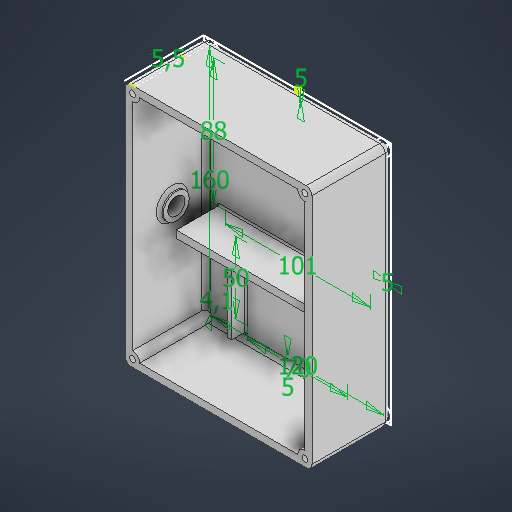
# Autodesk Inventor part: CaseBitDogLabV2
Saved by Autodesk Inventor 2027 (Build 310192000, 192)
## iProperties
Created: 2026-10-24
Part Number: CaseBitDogLabV2
Material: Genérico
Document SubType Name: Modeling
Designer: EspacoMaker
Density: 1 g/cm^3
Appearance: Padrão
Author: EspacoMaker
Autodesk Inventor part; units mm, degrees
ref_plane "YZ Plane" through (0, 0, 0) normal (1, 0, 0) x (0, 1, 0)
ref_plane "XZ Plane" through (0, 0, 0) normal (0, 1, 0) x (-1, 0, 0)
ref_plane "XY Plane" through (0, 0, 0) normal (0, 0, 1) x (1, 0, 0)
sketch "Esboço1" plane through (0, 0, 0) normal (0, 0, 1) x (1, 0, 0)
  line L0 (60, 80) -> (-60, 80)
  line L1 (-60, 80) -> (-60, -80)
  line L2 (-60, -80) -> (60, -80)
  line L3 (60, -80) -> (60, 80)
  line L4 (60, 80) -> (-60, -80) construction
  line L5 (-60, 80) -> (60, -80) construction
  line L6 (0, 80) -> (0, -80) construction
  line L7 (65, 85) -> (-65, 85)
  line L8 (-65, 85) -> (-65, -85)
  line L9 (-65, -85) -> (65, -85)
  line L10 (65, -85) -> (65, 85)
  line L11 (50.5, 75) -> (-50.5, 75) construction
  line L12 (-50.5, 75) -> (-50.5, -13) construction
  line L13 (-50.5, -13) -> (50.5, -13) construction
  line L14 (50.5, -13) -> (50.5, 75) construction
  line L15 (50.5, 75) -> (-50.5, -13) construction
  line L16 (-50.5, 75) -> (50.5, -13) construction
  line L17 (35, -25) -> (-35, -25) construction
  line L18 (-35, -25) -> (-35, -75) construction
  line L19 (-35, -75) -> (35, -75) construction
  line L20 (35, -75) -> (35, -25) construction
  line L21 (35, -25) -> (-35, -75) construction
  line L22 (-35, -25) -> (35, -75) construction
  circle A0 centre (-60, -80) radius 2.05
  circle A1 centre (-60, -80) radius 5
  circle A2 centre (60, -80) radius 2.05
  circle A3 centre (60, -80) radius 5
  line L23 (60, 0) -> (-60, 0) construction
  circle A4 centre (-60, 80) radius 2.05
  circle A5 centre (-60, 80) radius 5
  circle A6 centre (60, 80) radius 2.05
  circle A7 centre (60, 80) radius 5
  point P0 (0, 0)
  point P1 (0, 0)
  point P2 (0, 0)
  point P3 (0, 31)
  point P4 (0, -50)
  point P5 (-55, -80)
  point P6 (-60, -75)
  point P7 (60, -75)
  point P8 (55, -80)
  point P9 (55, 80)
  point P10 (60, 75)
  point P11 (-60, 75)
  point P12 (-55, 80)
  dimension "d0" = 120
  dimension "d1" = 160
  dimension "d8" = 5
  dimension "d9" = 101
  dimension "d10" = 88
  dimension "d11" = 5
  dimension "d12" = 70
  dimension "d13" = 50
  dimension "d14" = 5
  dimension "d21" = 4.1
  constraints: 48 end point, 11 midpoint, 8 centre point, 8 parallel, 4 perpendicular, 3 horizontal, 3 symmetric about line, 2 coincident, 2 point on line, 1 tangent, 7 other
  measures "d0" distance of L2.end L2.start
  measures "d1" distance of L2.start L0.end
  measures "d8" distance between parallel lines of L3 L10
  measures "d9" distance of L14.start L12.end
  measures "d10" distance of L12.end L12.start
  measures "d11" distance between parallel lines of L0 L11
  measures "d12" distance of L19.end L18.end
  measures "d13" distance of L18.end L18.start
  measures "d14" distance between parallel lines of L2 L19
  measures "d21" diameter of A0
extrude "Extrusão1" add sketch "Esboço1" along normal blind 4
extrude "Extrusão2" add sketch "Esboço1" along normal blind 55 contours A5 L1 A4 L0 | A5 L7 A7 L0 | L0 A4 L1 A5 | A4 L1 L0 | L0 L1 A4 | A7 L3 A6 L0 | L0 A6 L3 A7 | A5 L8 L7 | L1 A1 L8 A5 | A6 L3 L0 | L0 L3 A6 | L7 L10 A7 | A7 L10 A3 L3 | A1 L2 A0 L1 | L1 A0 L2 A1 | A3 L2 A2 L3 | L3 A2 L2 A3 | A1 L9 L8 | A0 L2 L1 | L1 L2 A0 | L2 A3 L9 A1 | L10 L9 A3 | A2 L2 L3 | L3 L2 A2
fillet "Arredondamento1" radius 3 4 edges at (60, 0, 4) (0, 80, 4) (0, -80, 4) (-60, 0, 4)
fillet "Arredondamento2" radius 4 8 edges at (65, 85, 27.5) (65, 0, 0) (0, 85, 0) (-65, 85, 27.5) (-65, 0, 0) (-65, -85, 27.5) (0, -85, 0) (65, -85, 27.5)
sketch "Esboço2" plane through (0, 0, 55) normal (0, 0, 1) x (1, 0, 0)
  circle A0 centre (60, 80) radius 2.05 projected
  circle A1 centre (-60, 80) radius 2.05 projected
  circle A2 centre (60, -80) radius 2.05 projected
  circle A3 centre (-60, -80) radius 2.05 projected
  point P0 (0, 0)
extrude "Extrusão3" cut sketch "Esboço2" against normal blind 35
sketch "Esboço3" plane through (0, 0, 4) normal (0, 0, 1) x (1, 0, 0)
  line L0 (-50.5, -13) -> (50.5, -13) projected
  line L1 (-50.5, 75) -> (-50.5, -13) projected
  line L2 (50.5, 75) -> (-50.5, 75) projected
  line L3 (50.5, -13) -> (50.5, 75) projected
  line L4 (35, -75) -> (35, -25) projected
  line L5 (35, -25) -> (-35, -25) projected
  line L6 (-35, -25) -> (-35, -75) projected
  line L7 (-35, -75) -> (35, -75) projected
  line L8 (50.5, 70) -> (-50.5, 70)
  line L9 (-50.5, -8) -> (50.5, -8)
  line L10 (-35, -78) -> (35, -78)
  line L11 (32, -75) -> (32, -25)
  line L12 (-32, -25) -> (-32, -75)
  point P0 (0, 0)
  point P1 (-50.5, 70)
  dimension "d25" = 5
  dimension "d26" = 5
  dimension "d28" = 3
  dimension "d34" = 3
  dimension "d35" = 3
  constraints: 10 end point, 5 parallel
  measures "d25" distance between parallel lines of L2 L8
  measures "d26" distance between parallel lines of L0 L9
  measures "d28" distance between parallel lines of L7 L10
  measures "d34" distance between parallel lines of L4 L11
  measures "d35" distance between parallel lines of L6 L12
extrude "Extrusão4" add sketch "Esboço3" along normal blind 30 contours L1 L9 L3 L0 | L1 L2 L3 L8
extrude "Extrusão6" add sketch "Esboço3" along normal blind 10 contours L7 L11 L5 L4 | L7 L6 L5 L12
fillet "Arredondamento3" radius 1 16 edges at (0, 70, 4) (-50.5, 72.5, 4) (0, 75, 4) (50.5, 72.5, 4) (0, -8, 4) (0, -13, 4) (50.5, -10.5, 4) (-50.5, -10.5, 4) (-35, -50, 4) (-32, -50, 4) (-33.5, -25, 4) (-33.5, -75, 4) (35, -50, 4) (33.5, -75, 4) (32, -50, 4) (33.5, -25, 4)
sketch "Esboço4" plane through (-65, -81, 4) normal (-1, 0, 0) x (0, 0, 1)
  line L0 (51, 166) -> (51, 162) construction
  line L1 (-4, 162) -> (-4, 0) construction
  line L2 (51, 162) -> (-4, 162) construction
  line L3 (-4, 162) -> (-4, 0) construction
  line L4 (-4, 0) -> (51, 0) construction
  line L5 (51, 0) -> (51, 162) construction
  line L6 (51, 162) -> (-4, 0) construction
  circle A0 centre (23.5, 81) radius 6
  circle A1 centre (23.5, 81) radius 9
  point P0 (-4, 81)
  dimension "d39" = 12
  dimension "d40" = 3
  constraints: 10 end point, 2 centre point, 2 parallel, 1 horizontal, 1 midpoint, 1 perpendicular
  measures "d39" diameter of A0
  measures "d40" radial gap between concentric circles of A0 A1
extrude "Extrusão7" cut sketch "Esboço4" against normal blind 5 contours A0
extrude "Extrusão8" add sketch "Esboço4" along normal blind 3 and the other way blind 8
fillet "Arredondamento4" radius 2 2 edges at (-65, 0, 18.5) (-60, 0, 18.5)
sketch "Esboço5" plane through (-61, 85, 4) normal (0, 1, 0) x (1, 0, 0)
  line L0 (3.05, -16) -> (-1.05, -16) projected
  line L1 (3.05, -51) -> (-1.05, -51) projected
  line L2 (3.05, -51) -> (3.05, 4) construction
  line L3 (122, 4) -> (0, 4) projected
  line L4 (-1.05, -51) -> (-1.05, 4) construction
  line L5 (1, -51) -> (1, 4) construction
  line L6 (-4.5, -51) -> (-4.5, 4)
  point P0 (61, 4)
  dimension "d48" = 5.5
  constraints: 8 end point, 2 point on line, 2 vertical, 1 midpoint, 1 parallel, 1 perpendicular
  measures "d48" distance between parallel lines of L5 L6
